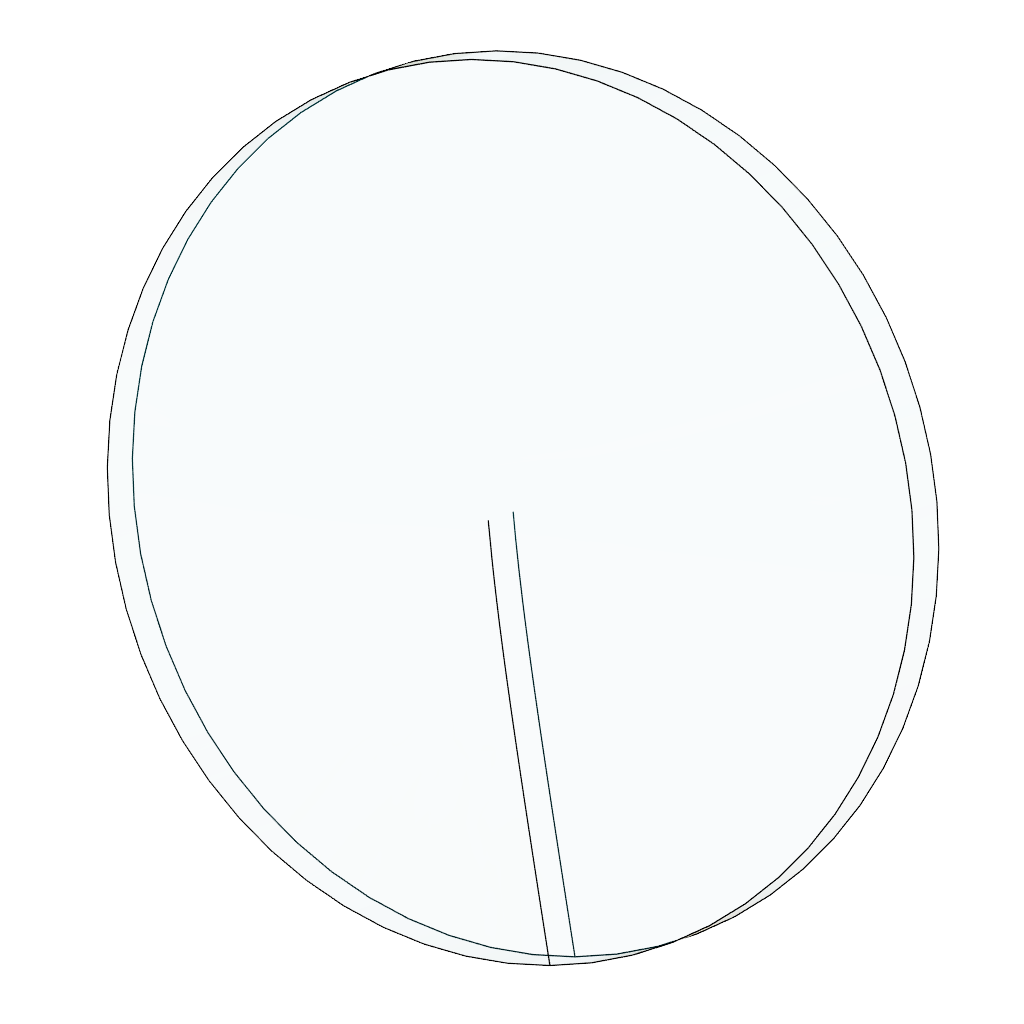
v1.1 master assembly (Autodesk Fusion 360 archive; units mm, degrees)
design "watch crystal"
Autodesk Fusion 360 part; units mm, degrees
sketch "Sketch1" plane through (0, 0, 0) normal (0, 0, 1) x (1, 0, 0)
  circle A0 centre (0, 0) radius 16.25 construction
  circle A1 centre (0, 0) radius 17.75
  dimension "d8" = 32.5
  dimension "d9" = 35.5
  constraint coincident A0.centre A1.centre
  constraint concentric A0 A1
  measures "d8" diameter of A0
  measures "d9" diameter of A1
sketch "Sketch2" plane through (0, 0, 0) normal (1, 0, 0) x (0, 1, 0)
  line L0 (0, 0) -> (0, 1.8) construction
  line L1 (17.75, 0) -> (-17.75, 0)
  spline S0 degree 2 poles (17.75, 0) (-0.0002, 2.3989) (-17.75, 0) knots 0 0 0 3.56819 3.56819 3.56819 weights 1 3 1
  line L2 (17.75, 0) -> (17.75, 2.0182)
  line L3 (-17.75, 0) -> (-17.75, 2.0182)
  spline S1 degree 3 poles (17.75, 2.0182) (15.4045, 2.3346) (13.7477, 2.5513) (12.3653, 2.7272) (10.2445, 2.9972) (8.7997, 3.167) (7.585, 3.2996) (5.6869, 3.5067) (4.3867, 3.6178) (3.2218, 3.6917) (0.8264, 3.8436) (-0.8719, 3.8429) (-3.2794, 3.688) (-4.376, 3.6175) (-5.6004, 3.5131) (-7.3222, 3.3281) (-8.3513, 3.2175) (-9.555, 3.0785) (-11.1828, 2.8761) (-12.4774, 2.7151) (-14.0263, 2.5161) (-16.198, 2.2264) (-16.6802, 2.1621) (-17.1947, 2.0931) (-17.75, 2.0182) knots 0.009059 0.009059 0.009059 0.009059 0.249681 0.249681 0.249681 0.618838 0.618838 0.618838 1.195687 1.195687 1.195687 2.381939 2.381939 2.381939 2.922269 2.922269 2.922269 3.24523 3.24523 3.24523 3.502088 3.502088 3.502088 3.559125 3.559125 3.559125 3.559125
  line L4 (0.0015, 3.8049) -> (0, 1.7992)
  dimension "d10" = 1.8
  constraint coincident L0.start origin
  constraint vertical L0
  constraint coincident L1.end S0.end
  constraint coincident L1.start S0.start
  constraint perpendicular L1 L2
  constraint perpendicular L1 L3
  constraint coincident S1 L4.start
  constraint coincident S0 L4.end
  constraint coincident L0 L4.end
  measures "d10" distance of L0.start L0.end
revolve "Revolve1" add sketch "Sketch2" angle 360 about axis through (0, 0.0015, 3.8049) along (0, -0.000739, -1) contours S0 L3 S1 L4
equation "disp_actual_displayed_dia = 32.5 mm" comment "actual dia where pixels are shown | MUST MATCH in: display bezel, main body front, watch crystal. Change all together."
equation "watch_crystal_dia = 35.5 mm" comment "MUST MATCH in: display bezel, main body back, main body front, watch crystal, wings source (sketches). Change all together."
equation "d8 = disp_actual_displayed_dia"
equation "d9 = watch_crystal_dia"
named bodies: "watch crystal"

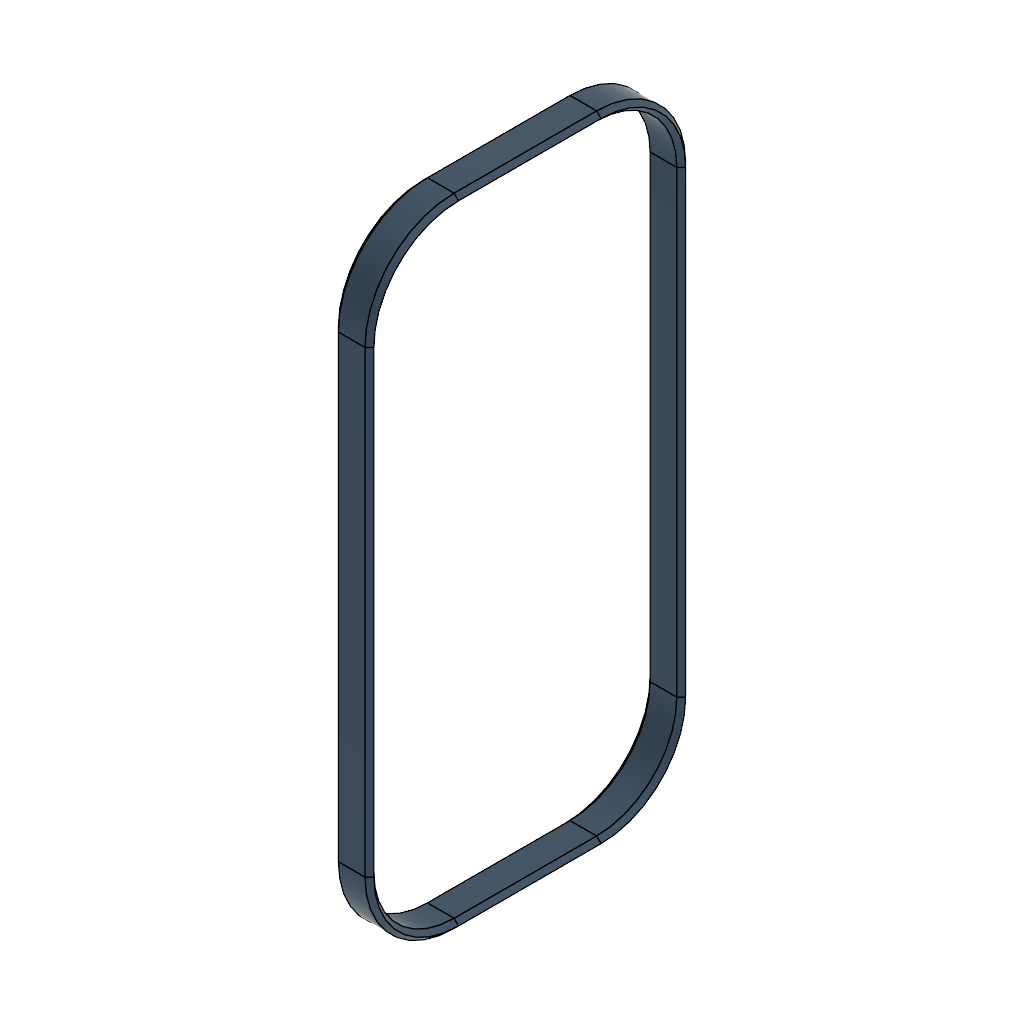
design "joint sleeve"
Autodesk Fusion 360 part; units mm, degrees
sketch "joint sleeve" plane through (0, 0, 0) normal (1, 0, 0) x (0, 1, 0)
  line L0 (0, 63.5) -> (0, 12)
  line L1 (25.5251, 7.9749) -> (25.5251, 2) construction
  line L2 (9.5251, 67.5251) -> (5.7467, 71.3036)
  line L3 (9.0338, 7.3578) -> (9.0338, 2.45) construction
  arc A0 (12, 73.5) -> (2, 63.5) centre (12, 63.5) ccw
  circle A1 centre (28, 70) radius 3.5
  circle A2 centre (28, 5.5) radius 3.5
  line L4 (31.5, 5.5) -> (31.5, 2.6325)
  line L5 (34.7175, 3.1612) -> (35.3581, 2.5206)
  arc A3 (12, 75.5) -> (0, 63.5) centre (12, 63.5) ccw
  circle A4 centre (12, 5.5) radius 3.5
  line L6 (35.7782, 71.2782) -> (34.7175, 72.3388)
  line L7 (35.0711, 4.9289) -> (36.4853, 3.5147)
  line L8 (34.7175, 72.3388) -> (35.3581, 72.9794)
  line L9 (25.5251, 7.9749) -> (19.5503, 2)
  line L10 (12, 2) -> (28, 2)
  arc A5 (38, 63.5) -> (28, 73.5) centre (28, 63.5) ccw
  line L11 (38, 12) -> (38, 63.5)
  line L12 (2, 63.5) -> (2, 12)
  line L13 (9.5251, 67.5251) -> (9.5251, 73.1889) construction
  line L14 (9.0338, 7.3578) -> (5.8167, 4.1408)
  line L15 (28, 73.5) -> (12, 73.5)
  line L16 (12, 0) -> (28, 0)
  line L17 (35.0711, 70.5711) -> (36.4853, 71.9853)
  line L18 (40, 12) -> (40, 63.5)
  line L19 (15.5, 70) -> (15.5, 73.5)
  circle A6 centre (12, 70) radius 3.5
  circle A7 centre (12, 5.5) radius 1.625
  arc A8 (40, 63.5) -> (28, 75.5) centre (28, 63.5) ccw
  circle A9 centre (28, 5.5) radius 1.625
  line L20 (28, 75.5) -> (12, 75.5)
  line L21 (31.5, 70) -> (31.5, 72.8675)
  line L22 (25.5251, 67.5251) -> (19.5503, 73.5)
  line L23 (25.5251, 67.5251) -> (29.4142, 67.5251) construction
  line L24 (35.7782, 4.2218) -> (34.7175, 3.1612)
  arc A10 (2, 12) -> (12, 2) centre (12, 12) ccw
  arc A11 (0, 12) -> (12, 0) centre (12, 12) ccw
  arc A12 (28, 2) -> (38, 12) centre (28, 12) ccw
  arc A13 (28, 0) -> (40, 12) centre (28, 12) ccw
  circle A14 centre (12, 70) radius 1.625
  line L25 (15.5, 5.5) -> (15.5, 2)
  circle A15 centre (28, 70) radius 1.625
  line L26 (12, 3) -> (28, 3)
  arc A16 (28, 3) -> (37, 12) centre (28, 12) ccw
  line L27 (37, 12) -> (37, 63.5)
  arc A17 (37, 63.5) -> (28, 72.5) centre (28, 63.5) ccw
  line L28 (28, 72.5) -> (12, 72.5)
  arc A18 (12, 72.5) -> (3, 63.5) centre (12, 63.5) ccw
  line L29 (3, 63.5) -> (3, 12)
  arc A19 (3, 12) -> (12, 3) centre (12, 12) ccw
  line L30 (8.5, 70) -> (8.5, 72.8675)
  line L31 (24.5, 70.0058) -> (24.5058, 73.5)
  line L32 (8.5, 5.5) -> (8.5, 2.6325)
  line L33 (24.5, 5.5) -> (24.5, 2)
  line L34 (8.5, 2.6325) -> (8.5, 0.5218)
  line L35 (15.5, 2) -> (15.5, 0)
  line L36 (24.5, 2) -> (24.5, 0)
  line L37 (31.5, 2.6325) -> (31.5, 0.5218)
  line L38 (8.5, 72.8675) -> (8.5, 74.9782)
  line L39 (15.5, 73.5) -> (15.5, 75.5)
  line L40 (24.5058, 73.5) -> (24.5058, 75.5)
  line L41 (31.5, 72.8675) -> (31.5, 74.9782)
  line L42 (3, 37.75) -> (37, 37.75) construction
  line L43 (3, 55.75) -> (37, 55.75) construction
  line L44 (3, 19.75) -> (37, 19.75) construction
  line L45 (9.3473, 36.75) -> (30.6527, 36.75)
  arc A20 (30.6527, 36.75) -> (30.6527, 38.75) centre (30.6527, 37.75) ccw
  line L46 (30.6527, 38.75) -> (9.3473, 38.75)
  arc A21 (9.3473, 38.75) -> (9.3473, 36.75) centre (9.3473, 37.75) ccw
  line L47 (9.3473, 37.75) -> (30.6527, 37.75) construction
  arc A22 (30.6527, 12.75) -> (30.6527, 14.75) centre (30.6527, 13.75) ccw
  line L48 (9.3473, 12.75) -> (30.6527, 12.75)
  arc A23 (9.3473, 14.75) -> (9.3473, 12.75) centre (9.3473, 13.75) ccw
  line L49 (30.6527, 14.75) -> (9.3473, 14.75)
  line L50 (9.3473, 13.75) -> (30.6527, 13.75) construction
  arc A24 (30.6527, 24.75) -> (30.6527, 26.75) centre (30.6527, 25.75) ccw
  line L51 (9.3473, 24.75) -> (30.6527, 24.75)
  arc A25 (9.3473, 26.75) -> (9.3473, 24.75) centre (9.3473, 25.75) ccw
  line L52 (30.6527, 26.75) -> (9.3473, 26.75)
  line L53 (9.3473, 25.75) -> (30.6527, 25.75) construction
  arc A26 (30.6527, 30.75) -> (30.6527, 32.75) centre (30.6527, 31.75) ccw
  line L54 (9.3473, 30.75) -> (30.6527, 30.75)
  arc A27 (9.3473, 32.75) -> (9.3473, 30.75) centre (9.3473, 31.75) ccw
  line L55 (30.6527, 32.75) -> (9.3473, 32.75)
  line L56 (9.3473, 31.75) -> (30.6527, 31.75) construction
  arc A28 (30.6527, 42.75) -> (30.6527, 44.75) centre (30.6527, 43.75) ccw
  line L57 (9.3473, 42.75) -> (30.6527, 42.75)
  arc A29 (9.3473, 44.75) -> (9.3473, 42.75) centre (9.3473, 43.75) ccw
  line L58 (30.6527, 44.75) -> (9.3473, 44.75)
  line L59 (9.3473, 43.75) -> (30.6527, 43.75) construction
  arc A30 (30.6527, 48.75) -> (30.6527, 50.75) centre (30.6527, 49.75) ccw
  line L60 (9.3473, 48.75) -> (30.6527, 48.75)
  arc A31 (9.3473, 50.75) -> (9.3473, 48.75) centre (9.3473, 49.75) ccw
  line L61 (30.6527, 50.75) -> (9.3473, 50.75)
  line L62 (9.3473, 49.75) -> (30.6527, 49.75) construction
  arc A32 (30.6527, 60.75) -> (30.6527, 62.75) centre (30.6527, 61.75) ccw
  line L63 (9.3473, 60.75) -> (30.6527, 60.75)
  arc A33 (9.3473, 62.75) -> (9.3473, 60.75) centre (9.3473, 61.75) ccw
  line L64 (30.6527, 62.75) -> (9.3473, 62.75)
  line L65 (9.3473, 61.75) -> (30.6527, 61.75) construction
  point P0 (40, 0)
  point P1 (0, 75.5)
  point P2 (20, 37.75)
  point P3 (20, 13.75)
  point P4 (20, 25.75)
  point P5 (20, 31.75)
  point P6 (20, 43.75)
  point P7 (20, 49.75)
  point P8 (20, 61.75)
  dimension "d112" = -2
  dimension "d113" = 40
  dimension "d114" = 75.5
  dimension "d115" = 12
  dimension "d116" = 3.25
  dimension "d117" = 3.25
  dimension "d118" = 7
  dimension "d119" = 3.25
  dimension "d120" = 7
  dimension "d121" = 1.5
  dimension "d122" = 7
  dimension "d123" = 45
  dimension "d124" = 45
  dimension "d125" = 45
  dimension "d126" = 7
  dimension "d127" = 3.25
  dimension "d128" = 45
  dimension "d141" = 18
  dimension "d142" = 18
  dimension "d143" = 2
  dimension "d146" = 0
  dimension "d147" = 24
  constraint horizontal L16
  constraint vertical L18
  constraint horizontal L20
  constraint vertical L0
  constraint coincident P1 L20
  constraint coincident P1 L0
  constraint tangent A3 L20
  constraint tangent L0 A3
  constraint coincident origin L16
  constraint coincident origin L0
  constraint tangent L16 A11
  constraint tangent L0 A11
  constraint equal A3 A11
  constraint tangent L18 A8
  constraint tangent A8 L20
  constraint equal A3 A8
  constraint coincident P0 L16
  constraint coincident P0 L18
  constraint tangent L16 A13
  constraint tangent L18 A13
  constraint equal A3 A13
  constraint midpoint L17.start A5
  constraint midpoint L17.end A8
  constraint midpoint L7.start A12
  constraint midpoint L7.end A13
  constraint concentric A6 A14
  constraint vertical A0.start A6.centre
  constraint tangent L15 A6
  constraint concentric A2 A9
  constraint vertical L10.end A2.centre
  constraint tangent A2 L10
  constraint horizontal L23
  constraint coincident L22.end L15
  constraint coincident L14.end A10
  constraint coincident L1.start A2
  constraint coincident L9.end L10
  constraint coincident L19.start A6
  constraint coincident L19.end L15
  constraint tangent L19 A6
  constraint perpendicular L15 L19
  constraint coincident L21.end A5
  constraint vertical L21
  constraint coincident L25.end L10
  constraint perpendicular L10 L25
  constraint coincident L4.start A2
  constraint coincident L4.end A12
  constraint tangent A2 L4
  constraint parallel L4 L25
  constraint tangent A2 L9
  constraint coincident L2.start A6
  constraint coincident L2.end A0
  constraint tangent L2 A6
  constraint midpoint L6.start L17
  constraint perpendicular L6 L17
  constraint coincident L8.end A8
  constraint perpendicular L6 L8
  constraint midpoint L24.start L7
  constraint perpendicular L7 L24
  constraint coincident L5.end A13
  constraint perpendicular L5 L24
  constraint concentric A1 A15
  constraint tangent A1 L15
  constraint tangent A1 L22
  constraint coincident L22.start A1
  constraint coincident L13.end A0
  constraint vertical L13
  constraint coincident L3.end A10
  constraint vertical L3
  constraint concentric A4 A7
  constraint tangent A4 L10
  constraint coincident L3.start A4
  constraint coincident L1.end L10
  constraint perpendicular L1 L10
  constraint vertical A6.centre A4.centre
  constraint vertical A2.centre A1.centre
  constraint coincident L21.start A1
  constraint tangent A1 L21
  constraint tangent A4 L25
  constraint coincident L25.start A4
  constraint coincident A6 L30.start
  constraint coincident A0 L30.end
  constraint vertical L30
  constraint tangent A6 L30
  constraint coincident A1 L31.start
  constraint coincident L15 L31.end
  constraint tangent A1 L31
  constraint coincident A4 L32.start
  constraint coincident A10 L32.end
  constraint tangent A4 L32
  constraint vertical L32
  constraint coincident A2 L33.start
  constraint coincident L10 L33.end
  constraint tangent A2 L33
  constraint perpendicular L10 L33
  constraint coincident A11 L34.end
  constraint parallel L32 L34
  constraint coincident L16 L35.end
  constraint perpendicular L16 L35
  constraint coincident L16 L36.end
  constraint perpendicular L16 L36
  constraint coincident A13 L37.end
  constraint parallel L4 L37
  constraint coincident A3 L38.end
  constraint parallel L30 L38
  constraint coincident L20 L39.end
  constraint perpendicular L20 L39
  constraint coincident L20 L40.end
  constraint perpendicular L20 L40
  constraint coincident A8 L41.end
  constraint parallel L21 L41
  constraint midpoint L29 L42.start
  constraint midpoint L27 L42.end
  constraint perpendicular L27 L42
  constraint coincident L29 L43.start
  constraint coincident L27 L43.end
  constraint perpendicular L27 L43
  constraint coincident L29 L44.start
  constraint coincident L27 L44.end
  constraint perpendicular L27 L44
  constraint tangent L45 A20
  constraint tangent A20 L46
  constraint parallel L45 L46
  constraint tangent L46 A21
  constraint tangent L45 A21
  constraint coincident L42 A20.centre
  constraint parallel L42 L47
  constraint midpoint L42 P2
  constraint midpoint L47 P2
  measures "d113" distance of origin P0
  measures "d114" distance of origin P1
  measures "d115" radius of A3
  measures "d116" diameter of A15
  measures "d117" diameter of A14
  measures "d118" diameter of A6
  measures "d119" diameter of A9
  measures "d120" diameter of A2
  measures "d121" distance of L6.end L6.start
  measures "d122" diameter of A1
  measures "d123" angle of L15 L22
  measures "d124" angle of L2 L13
  measures "d125" angle of L3 L14
  measures "d126" diameter of A4
  measures "d127" diameter of A7
  measures "d128" angle of L1 L9
  measures "d141" distance of L42 L43
  measures "d142" distance of L42 L44
  measures "d143" diameter of A20
extrude "Extrude5" add sketch "joint sleeve" along normal blind 4 contours L2 A0 A18 L30 | A0 A6 A18 L30 | A4 A10 A19 L32 | L14 A10 A19 L32 | L15 L19 A6 L28 | A6 L28 A18 | L2 A0 L12 L14 A10 A18 L29 A19 | A4 L26 A19 | A4 L10 L25 L26 | L15 L19 L22 L28 | L9 L10 L25 L26 | L15 L22 L28 L31 | A1 L15 L28 L31 | A2 L10 L26 L33 | L9 L10 L26 L33 | A1 A5 L21 A17 | A1 A17 L28 | A2 L26 A16 | A2 L4 A12 A16 | L4 A5 L11 L21 A12 A16 L27 A17 picked at (11.5213, 72.8054) picked at (11.5213, 2.6946) picked at (28.4787, 72.8054) picked at (28.4787, 2.6946)
chamfer "Chamfer3" distance 0.5 angle 45 1 faces at (4, 37.3333, 46.3333) tangent chain off
chamfer "Chamfer3" distance 0.5 angle 45 1 faces at (0, 37.3333, 46.3333) tangent chain off
equation "disp_substrate_dia = 35.5 mm" comment "MUST MATCH in: joint sleeve, main body back, main body front, master exploded view, wings source (sketches). Change all together."
equation "bezel_frame_width = 4 mm" comment "MUST MATCH in: display bezel, joint sleeve, main body back, main body front, master exploded view, wings source (sketches). Change all together."
equation "distance_of_space_between_disp_holes = bezel_frame_width * 3" comment "MUST MATCH in: joint sleeve, main body back, main body front, master exploded view, wings source (sketches). Change all together."
equation "distance_bezel_to_end = bezel_frame_width * 3" comment "MUST MATCH in: joint sleeve, main body back, main body front, master exploded view, wings source (sketches). Change all together."
equation "main_body_width = disp_hole_dia * 5 + distance_of_space_between_disp_holes * 4 + distance_bezel_to_end * 2" comment "MUST MATCH in: joint sleeve, main body back, main body front, master exploded view, wings source (sketches). Change all together."
equation "disp_hole_dia = disp_substrate_dia" comment "MUST MATCH in: joint sleeve, main body back, main body front, master exploded view, wings source (sketches). Change all together."
equation "d41 = main_body_width"
equation "joint_sleeve_thickness = 1 mm" comment "MUST MATCH in: joint sleeve, main body front, wings source (sketches). Change all together."
equation "joint_sleeve_width = 4 mm" comment "MUST MATCH in: joint sleeve, main body front, main_body_back, wings source (sketches). Change all together."
equation "d70 = joint_sleeve_width"
equation "number_4_screw_thread_dia = 2.85 mm" comment "MUST MATCH in: joint sleeve, main body back, wings source (sketches). Change all together."
equation "d116 = number_4_screw_thread_dia + number_4_thread_clearance * 2"
equation "d117 = number_4_screw_thread_dia + number_4_thread_clearance * 2"
equation "d119 = number_4_screw_thread_dia + number_4_thread_clearance * 2"
equation "d127 = number_4_screw_thread_dia + number_4_thread_clearance * 2"
equation "d129 = -joint_sleeve_thickness"
equation "number_4_thread_clearance = 0.2 mm" comment "MUST MATCH in: joint sleeve, main body back, wings source (sketches). Change all together."
named bodies: "joint sleeve"

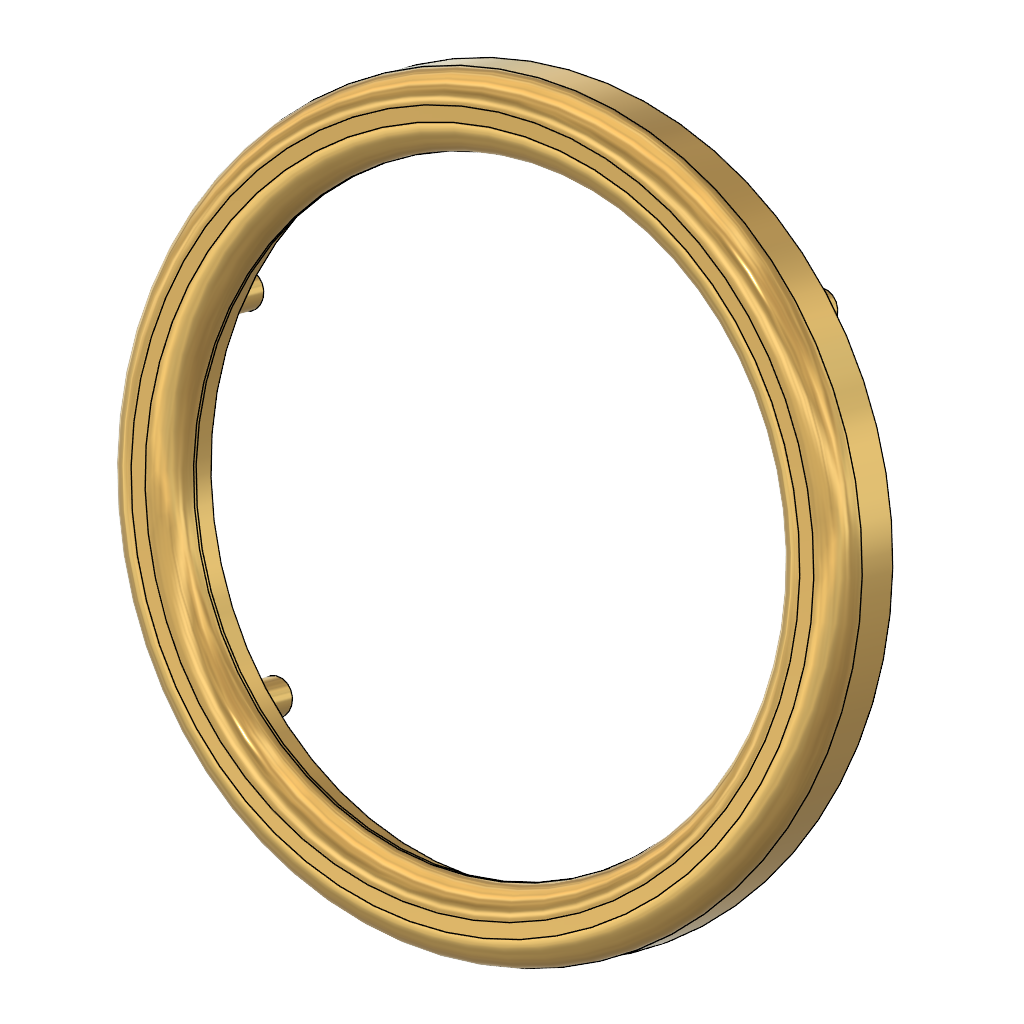
design "display bezel"
Autodesk Fusion 360 part; units mm, degrees
sketch "display bezel" plane through (0, 0, 0) normal (0, 0, 1) x (1, 0, 0)
  circle A0 centre (0, 0) radius 16.25 construction
  circle A1 centre (0, 0) radius 17.85
  circle A2 centre (0, 0) radius 17.1
  circle A3 centre (0, 0) radius 21.1
  circle A4 centre (0, 19) radius 1
  circle A5 centre (-16.4545, 9.5) radius 1
  circle A6 centre (-16.4545, -9.5) radius 1
  circle A7 centre (0, -19) radius 1
  circle A8 centre (16.4545, -9.5) radius 1
  circle A9 centre (16.4545, 9.5) radius 1
  dimension "d8" = 32.5
  dimension "d9" = 35.7
  dimension "d13" = 4
  dimension "d14" = 2
  dimension "d16" = 19
  dimension "d18" = 360
  constraint coincident A0.centre A1.centre
  constraint concentric A0 A1
  constraint vertical A0.centre A4.centre
  measures "d8" diameter of A0
  measures "d9" diameter of A1
  measures "d14" diameter of A4
  measures "d16" vertical distance of A0.centre A4.centre
extrude "Extrude1" add sketch "display bezel" along normal blind 4 contours A1 | A3 | A4 | A5 | A6 | A7 | A8 | A9
extrude "Extrude2" add sketch "display bezel" along normal blind 6.2 contours A4 | A5 | A6 | A7 | A8 | A9
extrude "Extrude3" cut sketch "display bezel" against normal blind 2 from surface at 4 contours A1
fillet "Fillet1" radius 1.6 1 edges at (-15.9428, 6.1836, 0)
fillet "Fillet1" radius 1.6 1 edges at (-19.6721, -7.6301, 0)
chamfer "Chamfer1" distance 0.2 distance2 0.75 1 edges at (-15.9428, -6.1836, 2) measured on face at (17.015, -1.7026, 1.8667) tangent chain off
chamfer "Chamfer2" distance 0.3 angle 45 6 edges at (-16.6075, 8.5118, 6.2) (-0.9323, 18.6384, 6.2) (15.6752, 10.1266, 6.2) (16.6075, -8.5118, 6.2) (0.9323, -18.6384, 6.2) (-15.6752, -10.1266, 6.2) tangent chain off
equation "disp_actual_displayed_dia = 32.5 mm" comment "actual dia where pixels are shown | MUST MATCH in: display bezel, main body front, watch crystal. Change all together."
equation "watch_crystal_dia = 35.5 mm" comment "MUST MATCH in: display bezel, main body back, main body front, watch crystal, wings source (sketches). Change all together."
equation "watch_crystal_thickness = 2 mm"
equation "d8 = disp_actual_displayed_dia"
equation "d9 = watch_crystal_dia + bezel_watch_crystal_clearance"
equation "d10 = -bezel_rabbet_wall_offset"
equation "bezel_frame_width = 4 mm" comment "MUST MATCH in: display bezel, joint sleeve, main body back, main body front, master exploded view, wings source (sketches). Change all together."
equation "bezel_thickness = 4 mm"
equation "d13 = bezel_frame_width"
equation "d14 = bezel_pin_dia"
equation "bezel_rabbet_wall_offset = 0.75 mm" comment "MUST MATCH in: display bezel, main body front. Change all together."
equation "d16 = ( watch_crystal_dia / 2 - bezel_rabbet_wall_offset ) + bezel_frame_width / 2"
equation "d19 = bezel_thickness"
equation "d21 = bezel_thickness + bezel_pin_length"
equation "bezel_pin_length = 2.2 mm"
equation "d26 = -watch_crystal_thickness"
equation "d29 = bezel_rabbet_wall_offset"
equation "bezel_watch_crystal_clearance = 0.2 mm" comment "amount extra to leave for fitting of crystal into bezel | MUST MATCH in: display bezel, main body front. Change all together."
equation "bezel_pin_dia = 2 mm"
equation "d41 = bezel_frame_width / 2 * 0.8"
equation "d43 = bezel_frame_width / 2 * 0.8"
named bodies: "display bezel"

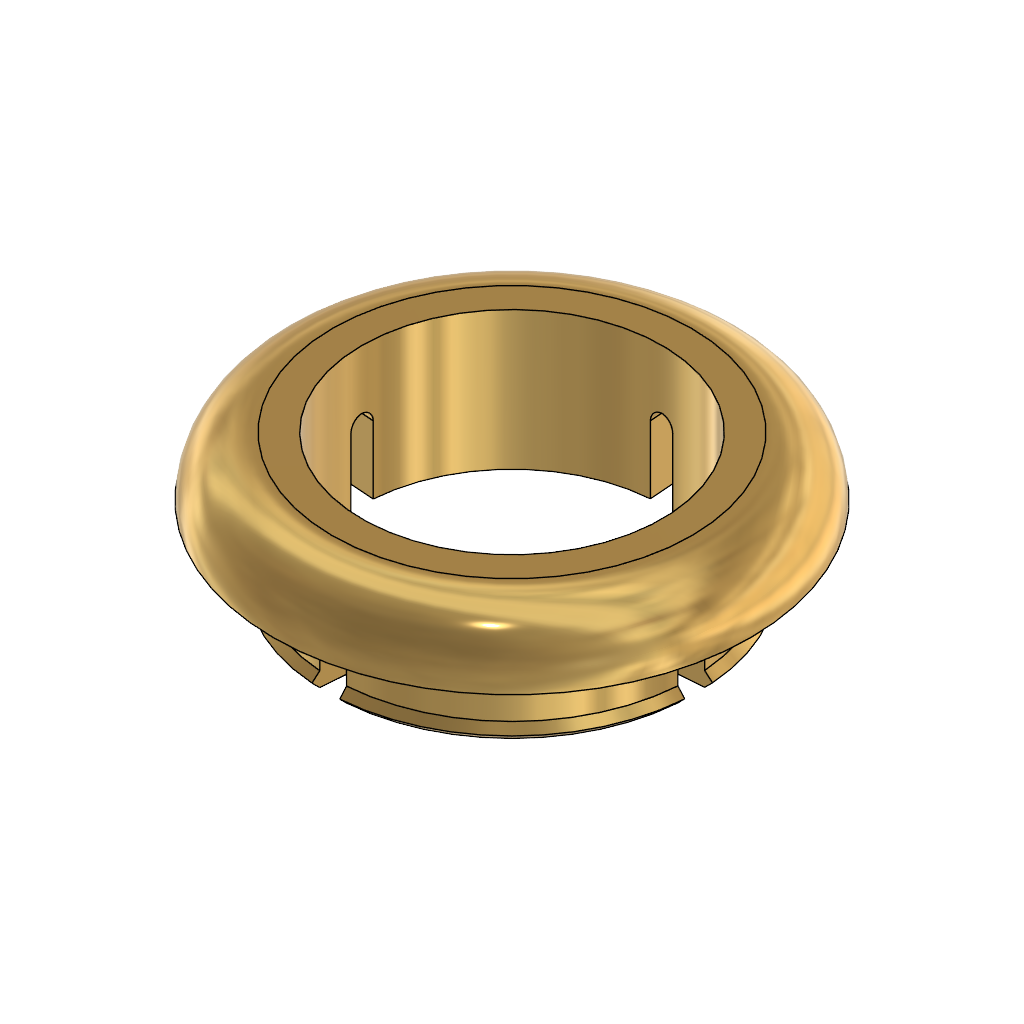
design "button bezel"
Autodesk Fusion 360 part; units mm, degrees
sketch "top" plane through (0, 0, 0) normal (0, 0, 1) x (1, 0, 0)
  circle A0 centre (0, 0) radius 6.1
  circle A1 centre (0, 0) radius 5.1
  circle A2 centre (0, 0) radius 8.1
  line L0 (0, 5.0932) -> (0, 6.1) construction
  circle A3 centre (0, 0) radius 6.35
  line L1 (-0.3725, -5.0864) -> (-0.4638, -6.333)
  line L2 (0.0063, -5.1) -> (0.0078, -6.35) construction
  line L3 (0.0063, -5.1) -> (0.0078, -6.35) construction
  line L4 (0.3851, -5.0854) -> (0.4795, -6.3319)
  line L5 (5.0864, -0.3725) -> (6.333, -0.4638)
  line L6 (5.0854, 0.3851) -> (6.3319, 0.4795)
  line L7 (0.3725, 5.0864) -> (0.4638, 6.333)
  line L8 (-0.3851, 5.0854) -> (-0.4795, 6.3319)
  line L9 (-5.0864, 0.3725) -> (-6.333, 0.4638)
  line L10 (-5.0854, -0.3851) -> (-6.3319, -0.4795)
  dimension "d35" = 12.2
  dimension "d37" = 3
  dimension "d49" = 0.25
  dimension "d51" = 360
  constraint coincident A0.centre A1.centre
  constraint coincident A0 L0.end
  constraint perpendicular A0 L0
  constraint vertical L0
  constraint coincident A1 L1.start
  constraint coincident A3 L1.end
  constraint perpendicular A1 L1
  constraint coincident A1 L2.start
  constraint coincident A3 L2.end
  constraint perpendicular A3 L2
  constraint symmetric L1.start L2 L4.start
  constraint symmetric L1.end L2 L4.end
  constraint symmetric L3.start L2 L2.start
  constraint symmetric L3.end L2 L2.end
  measures "d35" diameter of A0
extrude "Extrude1" add sketch "top" along normal blind 2 contours A0 A1 L5 L6 | A0 A3 L5 L6 | A0 A1 L6 L7 | A0 A3 L6 L7 | A0 A3 L4 L5 | A0 A1 L4 L5 | A0 A1 L7 L8 | A0 A3 L7 L8 | A0 A3 L1 L4 | A0 A1 L1 L4 | A0 A1 L8 L9 | A0 A3 L8 L9 | A0 A3 L1 L10 | A0 A1 L1 L10 | A0 A1 L9 L10 | A0 A3 L9 L10 | A2
fillet "Fillet1" radius 2 1 edges at (-7.5519, -2.9291, 2)
extrude "Extrude2" add sketch "top" against normal blind 2.7 contours A0 A1 L6 L7 | A0 A1 L4 L5 | A0 A1 L8 L9 | A0 A1 L1 L10
extrude "Extrude3" add sketch "top" along normal blind 0.25 from surface at -2.7 contours A0 A3 L6 L7 | A0 A3 L4 L5 | A0 A3 L8 L9 | A0 A3 L1 L10
chamfer "Chamfer1" distance 0.25 angle 45 4 edges at (-4.4957, 4.4846, -2.7) (4.4846, 4.4957, -2.7) (4.4957, -4.4846, -2.7) (-4.4846, -4.4957, -2.7) tangent chain off
chamfer "Chamfer1" distance 0.25 angle 45 4 edges at (4.3187, -4.308, -2.45) (-4.3187, 4.308, -2.45) (4.308, 4.3187, -2.45) (-4.308, -4.3187, -2.45) tangent chain off
fillet "Fillet2" radius 0.4 8 edges at (-0.409, -5.585, 0) (0.4228, -5.584, 0) (5.584, 0.4228, 0) (5.585, -0.409, 0) (-5.584, -0.4228, 0) (-5.585, 0.409, 0) (0.409, 5.585, 0) (-0.4228, 5.584, 0)
equation "main_body_wall_thickness = 2 mm" comment "MUST MATCH in: button bezel, main body back, main body front, wings source (sketches). Change all together."
equation "button_bezel_width = 3 mm"
equation "button_bezel_sleeve_thickness = 1 mm" comment "MUST MATCH in: button, button bezel. Change all together."
equation "d35 = button_hole_dia"
equation "d36 = -button_bezel_sleeve_thickness"
equation "d37 = button_bezel_width"
equation "d41 = button_bezel_thickness"
equation "button_bezel_thickness = 2 mm"
equation "d45 = button_bezel_thickness"
equation "button_bezel_clip_ridge_size = 0.25 mm"
equation "d47 = -( button_bezel_clip_depth )"
equation "d49 = button_bezel_clip_ridge_size"
equation "d53 = button_bezel_clip_ridge_size"
equation "d55 = button_bezel_clip_ridge_size"
equation "d56 = button_bezel_clip_ridge_size"
equation "button_bezel_clip_depth = main_body_wall_thickness + button_bezel_clip_ridge_size * 2 + 0.2 mm"
equation "button_hole_dia = 12.2 mm" comment "MUST MATCH in: button, button bezel, main body front. Change all together."
named bodies: "button bezel"
